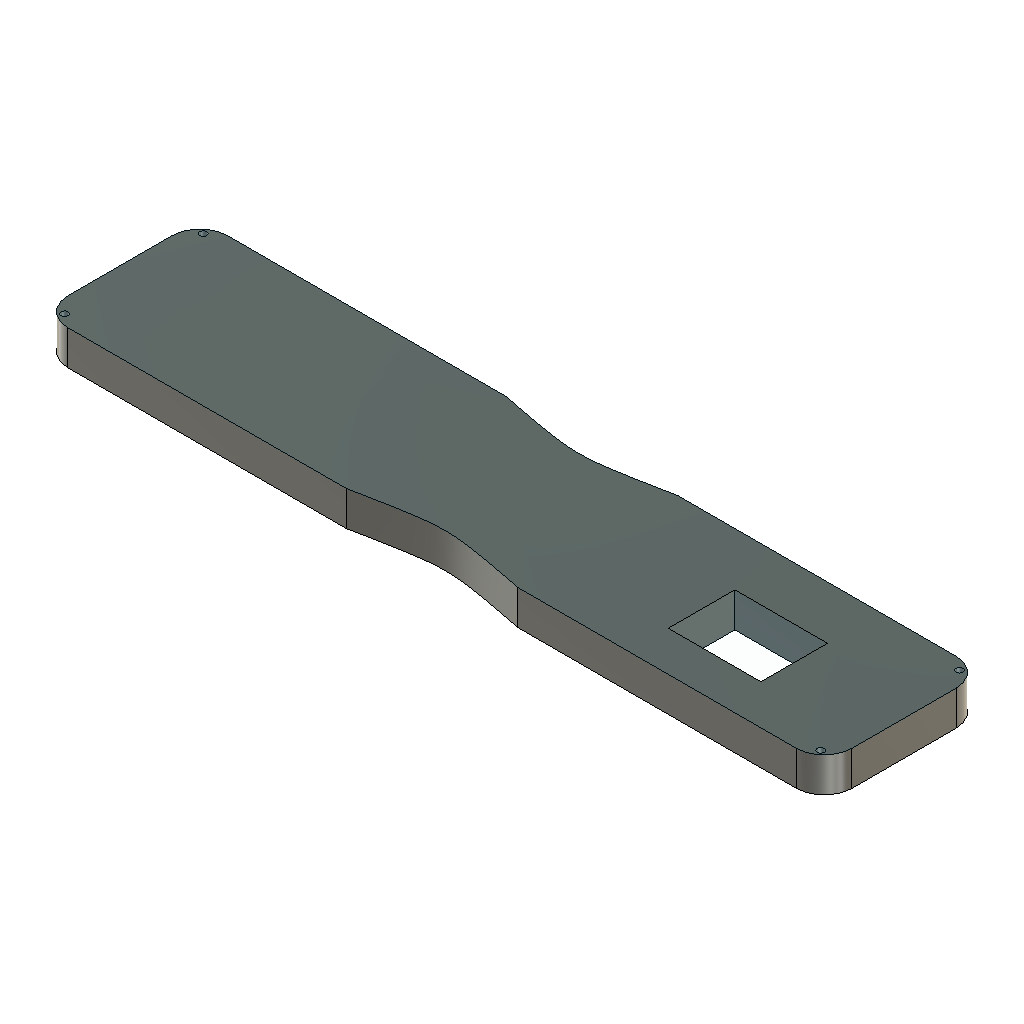
BODY FIX (Autodesk Fusion 360 archive; units mm, degrees)
design "ATAP"
part number: 2026-10-17-16-29-46-614
part number: 2026-10-17-16-30-07-760
Autodesk Fusion 360 part; units mm, degrees
sketch "Sketch1" plane through (0, 0, 0) normal (0, 0, 1) x (1, 0, 0) in component "BODY"
  line L0 (220, -5) -> (220, -35)
  line L1 (0, -35) -> (0, -5)
  spline S0 degree 2 poles (85, 0) (110, -5) (135, 0) knots 0 0 0 5.055937 5.055937 5.055937 weights 1 3 1
  spline S1 degree 2 poles (85, -40) (110, -35) (135, -40) knots 0 0 0 5.055937 5.055937 5.055937 weights 1 3 1
  line L2 (5, 0) -> (85, 0)
  line L3 (135, 0) -> (215, 0)
  line L4 (215, -40) -> (135, -40)
  line L5 (85, -40) -> (5, -40)
  arc A0 (5, 0) -> (0, -5) centre (5, -5) ccw
  arc A1 (0, -35) -> (5, -40) centre (5, -35) ccw
  arc A2 (220, -5) -> (215, 0) centre (215, -5) ccw
  arc A3 (215, -40) -> (220, -35) centre (215, -35) ccw
  line L6 (134.7029, 3) -> (215, 3)
  arc A4 (223, -5) -> (215, 3) centre (215, -5) ccw
  line L7 (223, -5) -> (223, -35)
  arc A5 (215, -43) -> (223, -35) centre (215, -35) ccw
  line L8 (215, -43) -> (134.7029, -43)
  spline S2 degree 3 poles (85.2971, -43) (85.3942, -42.9806) (85.4913, -42.9612) (85.5883, -42.9417) (88.7378, -42.3118) (91.0062, -41.8708) (92.8964, -41.5122) (95.6442, -40.991) (97.5671, -40.6494) (99.1726, -40.3809) (101.4565, -39.999) (103.0637, -39.7722) (104.4466, -39.6093) (106.751, -39.3377) (108.3904, -39.2469) (110.0735, -39.2501) (111.5654, -39.2529) (113.0434, -39.3326) (114.9845, -39.5446) (116.3031, -39.6887) (117.8205, -39.8922) (119.9263, -40.2327) (121.3153, -40.4572) (122.9539, -40.7401) (125.1691, -41.1497) (126.8436, -41.4593) (128.8369, -41.839) (131.5381, -42.3711) (132.4104, -42.543) (133.3594, -42.7313) (134.4117, -42.9417) (134.5087, -42.9612) (134.6058, -42.9806) (134.7029, -43) knots -0.009818 -0.009818 -0.009818 -0.009818 0 0 0 0.319276 0.319276 0.319276 0.783431 0.783431 0.783431 1.443693 1.443693 1.443693 2.543979 2.543979 2.543979 3.519329 3.519329 3.519329 4.181902 4.181902 4.181902 4.618919 4.618919 4.618919 4.949269 4.949269 4.949269 5.055937 5.055937 5.055937 5.065755 5.065755 5.065755 5.065755
  line L9 (85.2971, -43) -> (5, -43)
  arc A6 (-3, -35) -> (5, -43) centre (5, -35) ccw
  line L10 (-3, -35) -> (-3, -5)
  arc A7 (5, 3) -> (-3, -5) centre (5, -5) ccw
  line L11 (5, 3) -> (85.2971, 3)
  spline S3 degree 3 poles (85.2971, 3) (85.3942, 2.9806) (85.4913, 2.9612) (85.5883, 2.9417) (88.7378, 2.3118) (91.0062, 1.8708) (92.8964, 1.5122) (95.6442, 0.991) (97.5671, 0.6494) (99.1726, 0.3809) (101.4565, -0.001) (103.0637, -0.2278) (104.4466, -0.3907) (106.751, -0.6623) (108.3904, -0.7531) (110.0735, -0.7499) (111.5654, -0.7471) (113.0434, -0.6674) (114.9845, -0.4554) (116.3031, -0.3113) (117.8205, -0.1078) (119.9263, 0.2327) (121.3153, 0.4572) (122.9539, 0.7401) (125.1691, 1.1497) (126.8436, 1.4593) (128.8369, 1.839) (131.5381, 2.3711) (132.4104, 2.543) (133.3594, 2.7313) (134.4117, 2.9417) (134.5087, 2.9612) (134.6058, 2.9806) (134.7029, 3) knots -0.009818 -0.009818 -0.009818 -0.009818 0 0 0 0.319276 0.319276 0.319276 0.783431 0.783431 0.783431 1.443693 1.443693 1.443693 2.543979 2.543979 2.543979 3.519329 3.519329 3.519329 4.181902 4.181902 4.181902 4.618919 4.618919 4.618919 4.949269 4.949269 4.949269 5.055937 5.055937 5.055937 5.065755 5.065755 5.065755 5.065755
  point P0 (220, 0)
  point P1 (0, -40)
  dimension "d1" = 220
  dimension "d2" = 40
  dimension "d5" = 5
  dimension "d6" = 5
  dimension "d7" = 5
  dimension "d8" = 5
  dimension "d9" = -3
  constraint horizontal L2
  constraint vertical L0
  constraint horizontal L4
  constraint vertical L1
  constraint collinear L2 L3
  constraint collinear L4 L5
  constraint coincident origin L1
  constraint coincident origin L2
  constraint tangent L1 A0
  constraint tangent L2 A0
  constraint coincident P1 L1
  constraint coincident P1 L5
  constraint tangent L1 A1
  constraint tangent L5 A1
  constraint coincident P0 L0
  constraint coincident P0 L3
  constraint tangent L0 A2
  constraint tangent L3 A2
  constraint tangent L0 A3
  constraint tangent L4 A3
  measures "d1" distance of origin P0
  measures "d2" distance of origin P1
  measures "d5" radius of A0
  measures "d6" radius of A1
  measures "d7" radius of A2
  measures "d8" radius of A3
sketch "Sketch1 (2)" plane through (0, 0, 0) normal (0, 0, 1) x (1, 0, 0)
  circle A0 centre (1, 0) radius 1
  circle A1 centre (1, -40) radius 1
  circle A2 centre (219, 0) radius 1
  circle A3 centre (219, -40) radius 1
  dimension "d10" = 2
  dimension "d11" = 2
  dimension "d12" = 2
  dimension "d13" = 2
  measures "d10" diameter of A0
  measures "d11" diameter of A1
  measures "d12" diameter of A2
  measures "d13" diameter of A3
extrude "Extrude1" add sketch "Sketch1" along normal blind 10 contours L0 L1 S0 S1 L2 L3 L4 L5 A0 A1 A2 A3 | L6 A4 L7 A5 L8 S2 L9 A6 L10 A7 L11 S3
sketch "Sketch2" plane through (0, 0, 10) normal (0, 0, 1) x (-1, 0, 0)
  arc A0 (-5, -3) -> (3, 5) centre (-5, 5) ccw
  line L0 (3, 5) -> (3, 35)
  arc A1 (3, 35) -> (-5, 43) centre (-5, 35) ccw
  line L1 (-5, 43) -> (-85.2971, 43)
  spline S0 degree 3 poles (-85.2971, 43) (-85.3942, 42.9806) (-85.4913, 42.9612) (-85.5883, 42.9417) (-88.7378, 42.3118) (-91.0062, 41.8708) (-92.8964, 41.5122) (-95.6442, 40.991) (-97.5671, 40.6494) (-99.1726, 40.3809) (-101.4565, 39.999) (-103.0637, 39.7722) (-104.4466, 39.6093) (-106.751, 39.3377) (-108.3904, 39.2469) (-110.0735, 39.2501) (-111.5654, 39.2529) (-113.0434, 39.3326) (-114.9845, 39.5446) (-116.3031, 39.6887) (-117.8205, 39.8922) (-119.9263, 40.2327) (-121.3153, 40.4572) (-122.9539, 40.7401) (-125.1691, 41.1497) (-126.8436, 41.4593) (-128.8369, 41.839) (-131.5381, 42.3711) (-132.4104, 42.543) (-133.3594, 42.7313) (-134.4117, 42.9417) (-134.5087, 42.9612) (-134.6058, 42.9806) (-134.7029, 43) knots -0.009818 -0.009818 -0.009818 -0.009818 0 0 0 0.319276 0.319276 0.319276 0.783431 0.783431 0.783431 1.443693 1.443693 1.443693 2.543979 2.543979 2.543979 3.519329 3.519329 3.519329 4.181902 4.181902 4.181902 4.618919 4.618919 4.618919 4.949269 4.949269 4.949269 5.055937 5.055937 5.055937 5.065755 5.065755 5.065755 5.065755
  line L2 (-134.7029, 43) -> (-215, 43)
  arc A2 (-215, 43) -> (-223, 35) centre (-215, 35) ccw
  line L3 (-223, 35) -> (-223, 5)
  arc A3 (-223, 5) -> (-215, -3) centre (-215, 5) ccw
  line L4 (-215, -3) -> (-134.7029, -3)
  spline S1 degree 3 poles (-134.7029, -3) (-134.6058, -2.9806) (-134.5087, -2.9612) (-134.4117, -2.9417) (-133.3594, -2.7313) (-132.4104, -2.543) (-131.5381, -2.3711) (-128.8369, -1.839) (-126.8436, -1.4593) (-125.1691, -1.1497) (-122.9539, -0.7401) (-121.3153, -0.4572) (-119.9263, -0.2327) (-117.8205, 0.1078) (-116.3031, 0.3113) (-114.9845, 0.4554) (-113.0434, 0.6674) (-111.5654, 0.7471) (-110.0735, 0.7499) (-108.3904, 0.7531) (-106.751, 0.6623) (-104.4466, 0.3907) (-103.0637, 0.2278) (-101.4565, 0.001) (-99.1726, -0.3809) (-97.5671, -0.6494) (-95.6442, -0.991) (-92.8964, -1.5122) (-91.0062, -1.8708) (-88.7378, -2.3118) (-85.5883, -2.9417) (-85.4913, -2.9612) (-85.3942, -2.9806) (-85.2971, -3) knots -5.065755 -5.065755 -5.065755 -5.065755 -5.055937 -5.055937 -5.055937 -4.949269 -4.949269 -4.949269 -4.618919 -4.618919 -4.618919 -4.181902 -4.181902 -4.181902 -3.519329 -3.519329 -3.519329 -2.543979 -2.543979 -2.543979 -1.443693 -1.443693 -1.443693 -0.783431 -0.783431 -0.783431 -0.319276 -0.319276 -0.319276 0 0 0 0.009818 0.009818 0.009818 0.009818
  line L5 (-85.2971, -3) -> (-5, -3)
  circle A4 centre (-1, 0) radius 1
  circle A5 centre (-1, 40) radius 1
  circle A6 centre (-219, 40) radius 1
  circle A7 centre (-219, 0) radius 1
  dimension "d16" = 2
  dimension "d17" = 2
  dimension "d18" = 2
  dimension "d19" = 2
  measures "d16" diameter of A4
  measures "d17" diameter of A5
  measures "d18" diameter of A6
  measures "d19" diameter of A7
extrude "Extrude2" cut sketch "Sketch2" against normal blind 14 contours A4
sketch "Sketch3" plane through (0, 0, 0) normal (0, 0, 1) x (1, 0, 0)
extrude "Extrude3" cut sketch "Sketch1 (2)" along normal blind 17 contours A1 | A2 | A3
sketch "Sketch4" plane through (0, 0, 10) normal (0, 0, 1) x (-1, 0, 0)
  circle A0 centre (-1, 40) radius 1
  circle A1 centre (-219, 0) radius 1
  circle A2 centre (-219, 40) radius 1
  circle A3 centre (-1, 0) radius 1
  arc A4 (-5, -3) -> (3, 5) centre (-5, 5) ccw
  line L0 (3, 5) -> (3, 35)
  arc A5 (3, 35) -> (-5, 43) centre (-5, 35) ccw
  line L1 (-5, 43) -> (-85.2971, 43)
  spline S0 degree 3 poles (-85.2971, 43) (-85.3942, 42.9806) (-85.4913, 42.9612) (-85.5883, 42.9417) (-88.7378, 42.3118) (-91.0062, 41.8708) (-92.8964, 41.5122) (-95.6442, 40.991) (-97.5671, 40.6494) (-99.1726, 40.3809) (-101.4565, 39.999) (-103.0637, 39.7722) (-104.4466, 39.6093) (-106.751, 39.3377) (-108.3904, 39.2469) (-110.0735, 39.2501) (-111.5654, 39.2529) (-113.0434, 39.3326) (-114.9845, 39.5446) (-116.3031, 39.6887) (-117.8205, 39.8922) (-119.9263, 40.2327) (-121.3153, 40.4572) (-122.9539, 40.7401) (-125.1691, 41.1497) (-126.8436, 41.4593) (-128.8369, 41.839) (-131.5381, 42.3711) (-132.4104, 42.543) (-133.3594, 42.7313) (-134.4117, 42.9417) (-134.5087, 42.9612) (-134.6058, 42.9806) (-134.7029, 43) knots -0.009818 -0.009818 -0.009818 -0.009818 0 0 0 0.319276 0.319276 0.319276 0.783431 0.783431 0.783431 1.443693 1.443693 1.443693 2.543979 2.543979 2.543979 3.519329 3.519329 3.519329 4.181902 4.181902 4.181902 4.618919 4.618919 4.618919 4.949269 4.949269 4.949269 5.055937 5.055937 5.055937 5.065755 5.065755 5.065755 5.065755
  line L2 (-134.7029, 43) -> (-215, 43)
  arc A6 (-215, 43) -> (-223, 35) centre (-215, 35) ccw
  line L3 (-223, 35) -> (-223, 5)
  arc A7 (-223, 5) -> (-215, -3) centre (-215, 5) ccw
  line L4 (-215, -3) -> (-134.7029, -3)
  spline S1 degree 3 poles (-134.7029, -3) (-134.6058, -2.9806) (-134.5087, -2.9612) (-134.4117, -2.9417) (-133.3594, -2.7313) (-132.4104, -2.543) (-131.5381, -2.3711) (-128.8369, -1.839) (-126.8436, -1.4593) (-125.1691, -1.1497) (-122.9539, -0.7401) (-121.3153, -0.4572) (-119.9263, -0.2327) (-117.8205, 0.1078) (-116.3031, 0.3113) (-114.9845, 0.4554) (-113.0434, 0.6674) (-111.5654, 0.7471) (-110.0735, 0.7499) (-108.3904, 0.7531) (-106.751, 0.6623) (-104.4466, 0.3907) (-103.0637, 0.2278) (-101.4565, 0.001) (-99.1726, -0.3809) (-97.5671, -0.6494) (-95.6442, -0.991) (-92.8964, -1.5122) (-91.0062, -1.8708) (-88.7378, -2.3118) (-85.5883, -2.9417) (-85.4913, -2.9612) (-85.3942, -2.9806) (-85.2971, -3) knots -5.065755 -5.065755 -5.065755 -5.065755 -5.055937 -5.055937 -5.055937 -4.949269 -4.949269 -4.949269 -4.618919 -4.618919 -4.618919 -4.181902 -4.181902 -4.181902 -3.519329 -3.519329 -3.519329 -2.543979 -2.543979 -2.543979 -1.443693 -1.443693 -1.443693 -0.783431 -0.783431 -0.783431 -0.319276 -0.319276 -0.319276 0 0 0 0.009818 0.009818 0.009818 0.009818
  line L5 (-85.2971, -3) -> (-5, -3)
sketch "Sketch5" plane through (0, 0, 10) normal (0, 0, 1) x (-1, 0, 0)
  line L0 (-166.5493, 12.2979) -> (-193.2493, 12.2979)
  line L1 (-193.2493, 12.2979) -> (-193.2493, 31.4979)
  line L2 (-193.2493, 31.4979) -> (-166.5493, 31.4979)
  line L3 (-166.5493, 31.4979) -> (-166.5493, 12.2979)
  line L4 (-166.5493, 12.2979) -> (-193.2493, 31.4979) construction
  line L5 (-193.2493, 12.2979) -> (-166.5493, 31.4979) construction
  point P0 (-179.8993, 21.8979)
  dimension "d24" = 26.7
  dimension "d25" = 19.2
  constraint horizontal L0
  constraint perpendicular L0 L1
  constraint parallel L0 L2
  constraint parallel L1 L3
  constraint coincident L4 P0
  constraint coincident L5 P0
  measures "d24" distance of L1.end L2.end
  measures "d25" distance of L0.end L1.end
extrude "Extrude4" cut sketch "Sketch5" against normal blind 20
component "BODY" placed x (1, 0, 0) y (0, 1, 0) z (0, 0, 1) at (0, 0, 0)

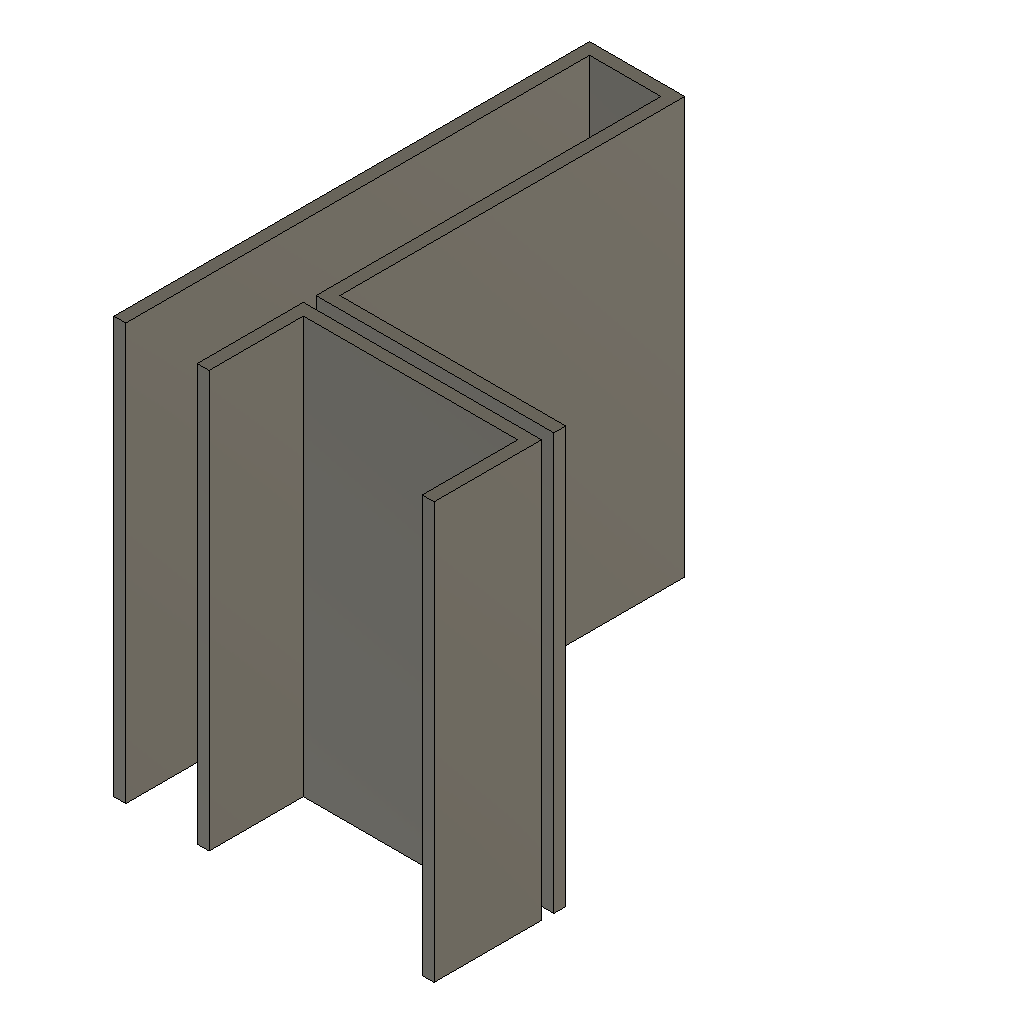
design "BRACKET"
part number: 2026-10-17-22-49-35-424
Autodesk Fusion 360 part; units mm, degrees
sketch "Sketch1" plane through (0, 0, 0) normal (0, 0, 1) x (1, 0, 0)
  line L0 (-0.5, 20) -> (0.5, 20)
  line L1 (0.5, -20) -> (-0.5, -20)
  line L2 (-0.5, 20) -> (0.5, -20) construction
  line L3 (0.475, 19) -> (-0.5, -20) construction
  line L4 (4.5, 20) -> (4.5, 19)
  line L5 (3.5, 19) -> (0.475, 19)
  line L6 (-0.475, 19) -> (-0.5, 19)
  line L7 (4.5, 20) -> (3.5, 20)
  line L8 (3.5, 19) -> (3.5, -10)
  line L9 (3.5, -10) -> (4.5, -10)
  line L10 (4.5, -9) -> (4.5, 20)
  line L11 (3.5, -10) -> (23.5, -10)
  line L12 (23.5, -10) -> (23.5, -9)
  line L13 (23.5, -9) -> (4.5, -9)
  line L14 (3.5, -9) -> (3.5, -10)
  line L15 (22.483, -12.0259) -> (4.4537, -12.0259)
  line L16 (3.4537, -12.0259) -> (3.4537, -11.0259)
  line L17 (3.4537, -11.0259) -> (23.483, -11.0259)
  line L18 (23.483, -11.0259) -> (23.483, -12.0259)
  line L19 (23.483, -11.0259) -> (22.483, -11.0259)
  line L20 (22.483, -12.0259) -> (22.483, -20.0589)
  line L21 (22.483, -20.0589) -> (23.483, -20.0589)
  line L22 (23.483, -20.0589) -> (23.483, -11.0259)
  line L23 (3.4537, -11.0259) -> (4.4537, -11.0259)
  line L24 (4.4537, -12.0259) -> (4.4537, -19.9527)
  line L25 (4.4537, -19.9527) -> (3.4537, -19.9527)
  line L26 (3.4537, -19.9527) -> (3.4537, -11.0259)
  line L27 (4.5, 20) -> (-2.5, 20)
  line L28 (-2.5, 19) -> (3.5, 19)
  line L29 (4.5, 19) -> (4.5, 20)
  line L30 (-2.5, 20) -> (-3.5, 20)
  line L31 (-3.5, 20) -> (-3.5, -20)
  line L32 (-3.5, -20) -> (-2.5, -20)
  line L33 (-2.5, -20) -> (-2.5, 19)
  dimension "d1" = 1
  dimension "d2" = 40
  dimension "d3" = 5
  dimension "d4" = 1
  dimension "d5" = 1
  dimension "d6" = 30
  dimension "d7" = 20
  dimension "d8" = 1
  dimension "d9" = 1
  dimension "d10" = 1
  dimension "d11" = 1
  dimension "d12" = 1
  dimension "d13" = 40
  constraint horizontal L0
  constraint parallel L0 L1
  constraint coincident L2 origin
  constraint coincident L3 origin
  constraint vertical L4
  constraint horizontal L5
  constraint coincident L2 L6.start
  constraint collinear L5 L6
  constraint horizontal L7
  constraint vertical L8
  constraint horizontal L9
  constraint vertical L10
  constraint horizontal L11
  constraint vertical L12
  constraint horizontal L13
  constraint vertical L14
  constraint horizontal L15
  constraint vertical L16
  constraint horizontal L17
  constraint vertical L18
  constraint horizontal L19
  constraint vertical L20
  constraint horizontal L21
  constraint vertical L22
  constraint horizontal L23
  constraint vertical L24
  constraint horizontal L25
  constraint vertical L26
  constraint horizontal L27
  constraint horizontal L28
  constraint vertical L29
  constraint horizontal L30
  constraint vertical L31
  constraint horizontal L32
  constraint vertical L33
  measures "d1" distance of L1.start L1.end
  measures "d2" distance of L0.end L1.start
  measures "d3" distance of L0.start L4.start
  measures "d4" distance of L0.start L6.end
  measures "d5" distance of L4.start L7.end
  measures "d6" distance of L4.start L9.end
  measures "d7" distance of L8.end L11.end
  measures "d8" distance of L8.end L14.start
  measures "d9" distance of L18.end L17.end
  measures "d10" distance of L17.end L19.end
  measures "d11" distance of L16.end L23.end
  measures "d12" distance of L27.end L30.end
  measures "d13" distance of L27.end L32.end
extrude "Extrude1" add sketch "Sketch1" along normal blind 35 makes body 1 at (10.1301, -11.0259, 11.6667) makes body 2 at (-3.5, 6.6667, 11.6667)

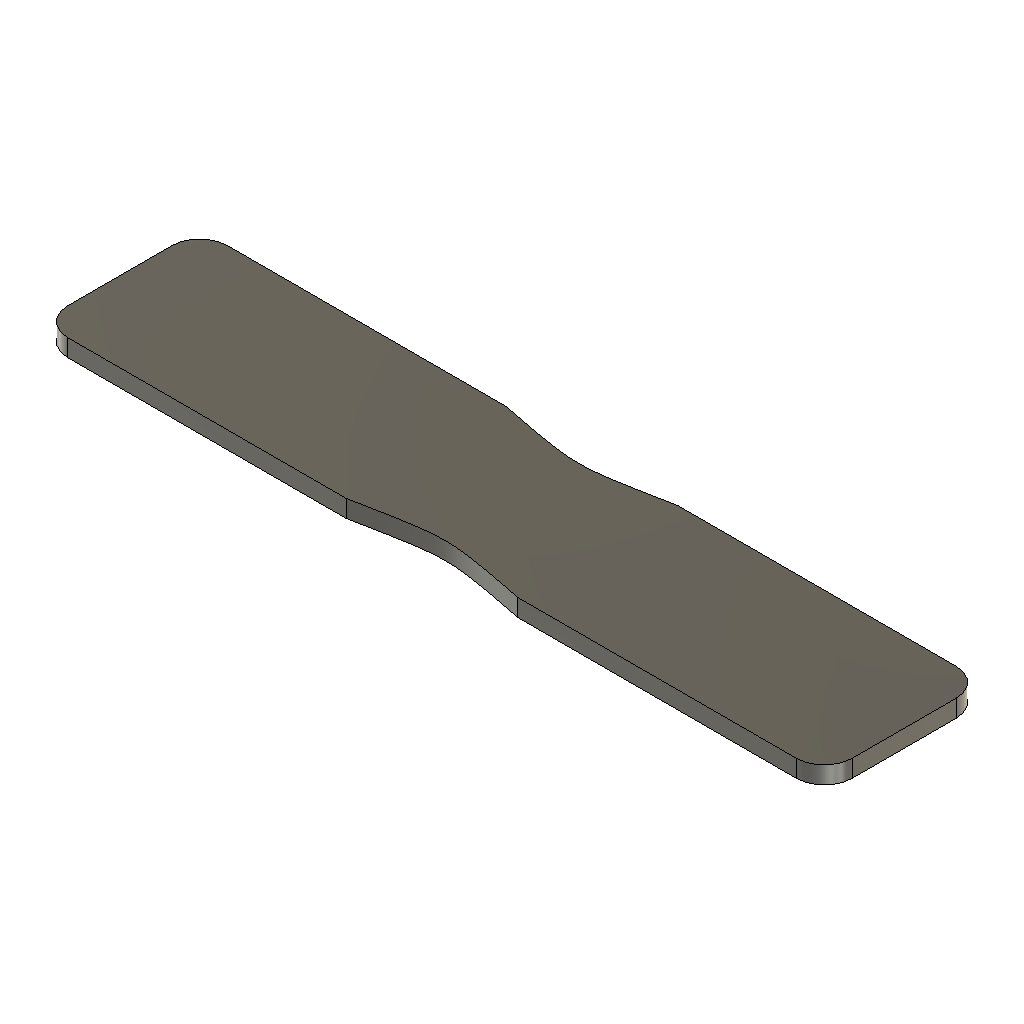
design "ALAS"
part number: 2026-10-17-16-28-50-860
part number: 2026-10-17-16-29-29-033
Autodesk Fusion 360 part; units mm, degrees
sketch "Sketch1" plane through (0, 0, 0) normal (0, 0, 1) x (1, 0, 0) in component "BODY"
  line L0 (220, -5) -> (220, -35)
  line L1 (0, -35) -> (0, -5)
  spline S0 degree 2 poles (85, 0) (110, -5) (135, 0) knots 0 0 0 5.055937 5.055937 5.055937 weights 1 3 1
  spline S1 degree 2 poles (85, -40) (110, -35) (135, -40) knots 0 0 0 5.055937 5.055937 5.055937 weights 1 3 1
  line L2 (5, 0) -> (85, 0)
  line L3 (135, 0) -> (215, 0)
  line L4 (215, -40) -> (135, -40)
  line L5 (85, -40) -> (5, -40)
  arc A0 (5, 0) -> (0, -5) centre (5, -5) ccw
  arc A1 (0, -35) -> (5, -40) centre (5, -35) ccw
  arc A2 (220, -5) -> (215, 0) centre (215, -5) ccw
  arc A3 (215, -40) -> (220, -35) centre (215, -35) ccw
  line L6 (134.7029, 3) -> (215, 3)
  arc A4 (223, -5) -> (215, 3) centre (215, -5) ccw
  line L7 (223, -5) -> (223, -35)
  arc A5 (215, -43) -> (223, -35) centre (215, -35) ccw
  line L8 (215, -43) -> (134.7029, -43)
  spline S2 degree 3 poles (85.2971, -43) (85.3942, -42.9806) (85.4913, -42.9612) (85.5883, -42.9417) (88.7378, -42.3118) (91.0062, -41.8708) (92.8964, -41.5122) (95.6442, -40.991) (97.5671, -40.6494) (99.1726, -40.3809) (101.4565, -39.999) (103.0637, -39.7722) (104.4466, -39.6093) (106.751, -39.3377) (108.3904, -39.2469) (110.0735, -39.2501) (111.5654, -39.2529) (113.0434, -39.3326) (114.9845, -39.5446) (116.3031, -39.6887) (117.8205, -39.8922) (119.9263, -40.2327) (121.3153, -40.4572) (122.9539, -40.7401) (125.1691, -41.1497) (126.8436, -41.4593) (128.8369, -41.839) (131.5381, -42.3711) (132.4104, -42.543) (133.3594, -42.7313) (134.4117, -42.9417) (134.5087, -42.9612) (134.6058, -42.9806) (134.7029, -43) knots -0.009818 -0.009818 -0.009818 -0.009818 0 0 0 0.319276 0.319276 0.319276 0.783431 0.783431 0.783431 1.443693 1.443693 1.443693 2.543979 2.543979 2.543979 3.519329 3.519329 3.519329 4.181902 4.181902 4.181902 4.618919 4.618919 4.618919 4.949269 4.949269 4.949269 5.055937 5.055937 5.055937 5.065755 5.065755 5.065755 5.065755
  line L9 (85.2971, -43) -> (5, -43)
  arc A6 (-3, -35) -> (5, -43) centre (5, -35) ccw
  line L10 (-3, -35) -> (-3, -5)
  arc A7 (5, 3) -> (-3, -5) centre (5, -5) ccw
  line L11 (5, 3) -> (85.2971, 3)
  spline S3 degree 3 poles (85.2971, 3) (85.3942, 2.9806) (85.4913, 2.9612) (85.5883, 2.9417) (88.7378, 2.3118) (91.0062, 1.8708) (92.8964, 1.5122) (95.6442, 0.991) (97.5671, 0.6494) (99.1726, 0.3809) (101.4565, -0.001) (103.0637, -0.2278) (104.4466, -0.3907) (106.751, -0.6623) (108.3904, -0.7531) (110.0735, -0.7499) (111.5654, -0.7471) (113.0434, -0.6674) (114.9845, -0.4554) (116.3031, -0.3113) (117.8205, -0.1078) (119.9263, 0.2327) (121.3153, 0.4572) (122.9539, 0.7401) (125.1691, 1.1497) (126.8436, 1.4593) (128.8369, 1.839) (131.5381, 2.3711) (132.4104, 2.543) (133.3594, 2.7313) (134.4117, 2.9417) (134.5087, 2.9612) (134.6058, 2.9806) (134.7029, 3) knots -0.009818 -0.009818 -0.009818 -0.009818 0 0 0 0.319276 0.319276 0.319276 0.783431 0.783431 0.783431 1.443693 1.443693 1.443693 2.543979 2.543979 2.543979 3.519329 3.519329 3.519329 4.181902 4.181902 4.181902 4.618919 4.618919 4.618919 4.949269 4.949269 4.949269 5.055937 5.055937 5.055937 5.065755 5.065755 5.065755 5.065755
  point P0 (220, 0)
  point P1 (0, -40)
  dimension "d1" = 220
  dimension "d2" = 40
  dimension "d5" = 5
  dimension "d6" = 5
  dimension "d7" = 5
  dimension "d8" = 5
  dimension "d9" = -3
  constraint horizontal L2
  constraint vertical L0
  constraint horizontal L4
  constraint vertical L1
  constraint collinear L2 L3
  constraint collinear L4 L5
  constraint coincident origin L1
  constraint coincident origin L2
  constraint tangent L1 A0
  constraint tangent L2 A0
  constraint coincident P1 L1
  constraint coincident P1 L5
  constraint tangent L1 A1
  constraint tangent L5 A1
  constraint coincident P0 L0
  constraint coincident P0 L3
  constraint tangent L0 A2
  constraint tangent L3 A2
  constraint tangent L0 A3
  constraint tangent L4 A3
  measures "d1" distance of origin P0
  measures "d2" distance of origin P1
  measures "d5" radius of A0
  measures "d6" radius of A1
  measures "d7" radius of A2
  measures "d8" radius of A3
extrude "Extrude1" add sketch "Sketch1" along normal blind 5 contours L0 L1 S0 S1 L2 L3 L4 L5 A0 A1 A2 A3 | L6 A4 L7 A5 L8 S2 L9 A6 L10 A7 L11 S3
component "BODY" placed x (1, 0, 0) y (0, 1, 0) z (0, 0, 1) at (0, 0, 0)
